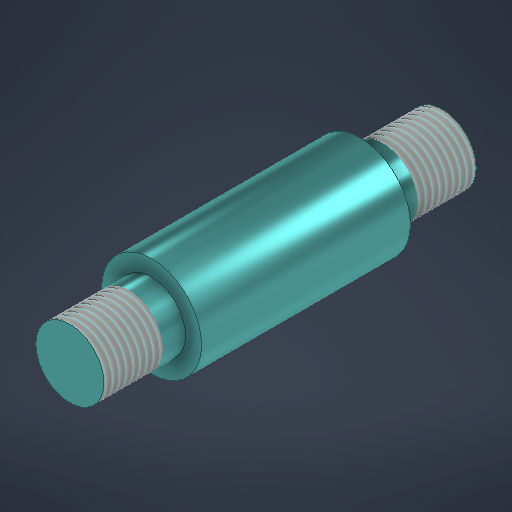
# Autodesk Inventor part: 5. Plate Spacer
Saved by Autodesk Inventor 2025.2 (Build 292293000, 293)
## iProperties
Created: 2025-05-09
Part Number: 5. Plate Spacer
Material: Steel, Mild
Document SubType Name: Modeling
Designer: trysm
Density: 7.85 g/cm^3
Appearance: Semi-Polished
Author: trysm
Autodesk Inventor part; units mm, degrees
ref_plane "YZ Plane" through (0, 0, 0) normal (1, 0, 0) x (0, 1, 0)
ref_plane "XZ Plane" through (0, 0, 0) normal (0, 1, 0) x (-1, 0, 0)
ref_plane "XY Plane" through (0, 0, 0) normal (0, 0, 1) x (1, 0, 0)
sketch "Sketch1" plane through (0, 0, 0) normal (0, 1, 0) x (-1, 0, 0)
  circle A0 centre (0, 0) radius 11
  circle A1 centre (0, 0) radius 7.5
  dimension "d0" = 22
  dimension "d1" = 15
  constraints: 2 centre point, 2 coincident
  measures "d0" diameter of A0
  measures "d1" diameter of A1
extrude "Extrusion1" add sketch "Sketch1" along normal mid plane 46
extrude "Extrusion2" add sketch "Sketch1" along normal mid plane 82 contours A1
thread "Thread1" size "M15x1.5" class "6g" standard "ANSI Metric M Profile" length 13
thread "Thread2" size "M15x1.5" class "6g" standard "ANSI Metric M Profile" length 13
body "Solid1"
